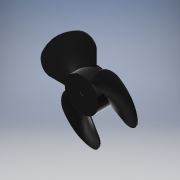
# Autodesk Inventor part: prop
Saved by Autodesk Inventor 2019 (Build 230136000, 136)
## iProperties
Created: 2015-07-08
Part Number: prop
Material: PC/ABS Plastic
Document SubType Name: Modeling
Designer: PARAMA DIPTYA W
Density: 0.357273 g/cm^3
Appearance: Smooth - Black
Mass: 4.844 g
Surface Area: 95.1159 cm^2
Volume: 13.5583 cm^3
Author: PARAMA DIPTYA W
Autodesk Inventor part; units mm, degrees
ref_plane "YZ Plane" through (0, 0, 0) normal (1, 0, 0) x (0, 1, 0)
ref_plane "XZ Plane" through (0, 0, 0) normal (0, 1, 0) x (-1, 0, 0)
sketch "Sketch1" plane through (0, 0, 0) normal (0, 1, 0) x (-1, 0, 0)
  circle A0 centre (0, 0) radius 15
  dimension "d0" = 30
  constraints: 1 centre point, 1 coincident
  measures "d0" diameter of A0
extrude "Extrusion1" add sketch "Sketch1" along normal blind 15
ref_plane "Work Plane4" through (0, 0, 0) normal (0, 0, 1) x (1, 0, 0)
sketch "Sketch3" plane through (0, 0, 0) normal (0, 0, 1) x (1, 0, 0)
  line L0 (-15, 0) -> (-15, 15) projected
  line L1 (-15, 0) -> (-40, 0)
  line L2 (-40, 0) -> (-40, 1)
  line L3 (-40, 1) -> (-15, 1)
  line L4 (-15, 1) -> (-15, 0)
  point P0 (0, 0)
  dimension "d19" = 1
  dimension "d20" = 25
  constraints: 8 end point, 2 parallel, 1 horizontal, 1 perpendicular, 1 point on line
  measures "d19" distance of L1.end L2.end
  measures "d20" distance of L2.end L3.end
coil "Coil2" sketch "Sketch3" operation add axis through (0, -10, 0) along (0, 1, 0) pitch 50 turns 0.25 hand right
fillet "Fillet2" radius 10 2 edges at (0, 13, 40) (-40, 0.5, 0)
pattern_circular "Circular Pattern2" count 3 over 360 about axis through (0, 0, 0) along (0, 1, 0) of "Coil2", "Fillet2"
sketch "Sketch4" plane through (0, 0, 0) normal (0, -1, 0) x (1, 0, 0)
  circle A0 centre (0, 0) radius 1.5
  line L0 (-0.0396, 1.4995) -> (-0.0396, -0.5005)
  line L1 (-1.4142, -0.5) -> (1.4142, -0.5)
  line L2 (1.4142, -0.5) -> (1.4142, -1.5)
  line L3 (1.4142, -1.5) -> (-1.4142, -1.5)
  line L4 (-1.4142, -1.5) -> (-1.4142, -0.5)
  dimension "d33" = 2
  constraints: 10 end point, 3 point on circle, 2 parallel, 1 centre point, 1 coincident, 1 horizontal, 1 perpendicular, 1 vertical
  measures "d33" distance of L0.start L0.end
extrude "Extrusion2" cut sketch "Sketch4" against normal through all contours A0 L1 L0 | L0 L1 A0
body "Solid1"
